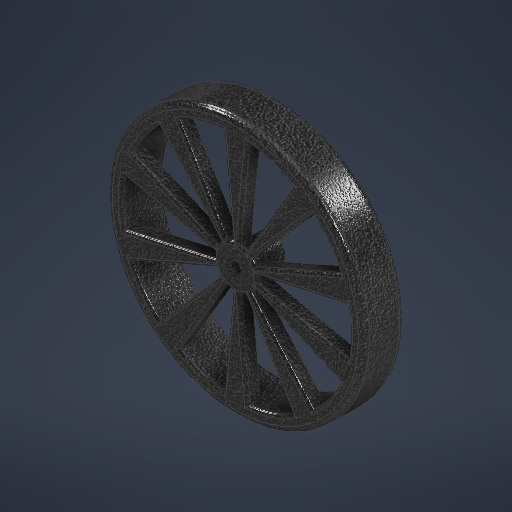
# Autodesk Inventor part: roues_3d_moteur_axe
Saved by Autodesk Inventor 2026 (Build 300175050, 175E)
## iProperties
Created: 2025-05-23
Part Number: roues_3d_moteur_axe
Material: Generisch
Document SubType Name: Modeling
Designer: karle
Density: 1 g/cm^3
Appearance: Vorgabe
Author: karle
Autodesk Inventor part; units mm, degrees
ref_plane "YZ Plane" through (0, 0, 0) normal (1, 0, 0) x (0, 1, 0)
sketch "Skizze1" plane through (0, 0, 0) normal (0, 0, 1) x (1, 0, 0)
  circle A0 centre (0, 0) radius 2
  circle A1 centre (0, 0) radius 45
  dimension "d0" = 4
  dimension "d1" = 90
  constraints: 2 centre point, 2 coincident
  measures "d0" diameter of A0
  measures "d1" diameter of A1
extrude "Extrusion1" add sketch "Skizze1" along normal mid plane 14.5
sketch "Skizze2" plane through (0, 0, -7.25) normal (0, 0, -1) x (-1, 0, 0)
  circle A0 centre (0, 0) radius 40
  circle A1 centre (0, 0) radius 5
  dimension "d4" = 10
  dimension "d5" = 80
  constraints: 2 centre point, 2 coincident
  measures "d4" diameter of A1
  measures "d5" diameter of A0
extrude "Extrusion2" cut sketch "Skizze2" against normal blind 10
sketch "Skizze3" plane through (0, 0, 7.25) normal (0, 0, 1) x (1, 0, 0)
  circle A0 centre (0, 0) radius 2 projected
  arc A1 (-7.4013, 1.213) -> (-7.4013, -1.213) centre (0, 0) ccw
  arc A2 (-39.1401, 8.2493) -> (-39.1401, -8.2493) centre (0, 0) ccw
  line L0 (-39.1401, 8.2493) -> (-7.4013, 1.213)
  line L1 (-7.4013, -1.213) -> (-39.1401, -8.2493)
  line L2 (0, 0) -> (-34.8454, 0)
  dimension "d8" = 80
  dimension "d9" = 15
  dimension "d12" = 25
  constraints: 6 end point, 4 point on circle, 2 centre point, 2 coincident, 1 horizontal, 1 other
  measures "d8" diameter of A2
  measures "d9" diameter of A1
  measures "d12" angle of L0 L1
extrude "Extrusion3" cut sketch "Skizze3" against normal blind 5 contours A1 L1 A2 L0
pattern_circular "Runde Anordnung1" count 10 over 360 about axis through (0, 0, -10) along (0, 0, 1) of "Extrusion3"
fillet "Rundung1" radius 1 40 edges at (-23.2707, 4.7311, 7.25) (-40, 0, 7.25) (-23.2707, -4.7311, 7.25) (-7.5, 0, 7.25) (-21.6073, 9.8506, 7.25) (-32.3607, 23.5114, 7.25) (-16.0455, 17.5057, 7.25) (-6.0676, 4.4084, 7.25) (-2.3176, 7.1329, 7.25) (-11.6906, 20.6697, 7.25) (-12.3607, 38.0423, 7.25) (-2.6915, 23.5937, 7.25) (2.6915, 23.5937, 7.25) (12.3607, 38.0423, 7.25) (11.6906, 20.6697, 7.25) (2.3176, 7.1329, 7.25) (16.0455, 17.5057, 7.25) (21.6073, 9.8506, 7.25) (6.0676, 4.4084, 7.25) (32.3607, 23.5114, 7.25) (40, 0, 7.25) (32.3607, -23.5114, 7.25) (21.6073, -9.8506, 7.25) (23.2707, -4.7311, 7.25) (23.2707, 4.7311, 7.25) (7.5, 0, 7.25) (6.0676, -4.4084, 7.25) (16.0455, -17.5057, 7.25) (11.6906, -20.6697, 7.25) (2.3176, -7.1329, 7.25) (2.6915, -23.5937, 7.25) (12.3607, -38.0423, 7.25) (-2.6915, -23.5937, 7.25) (-12.3607, -38.0423, 7.25) (-11.6906, -20.6697, 7.25) (-2.3176, -7.1329, 7.25) (-16.0455, -17.5057, 7.25) (-21.6073, -9.8506, 7.25) (-6.0676, -4.4084, 7.25) (-32.3607, -23.5114, 7.25)
sketch "Skizze4" plane through (0, 0, -7.25) normal (0, 0, -1) x (-1, 0, 0)
  circle A0 centre (0, 0) radius 7.5
  circle A1 centre (0, 0) radius 2
  dimension "d40" = 4
  dimension "d41" = 15
  constraints: 2 centre point, 2 coincident
  measures "d40" diameter of A1
  measures "d41" diameter of A0
extrude "Extrusion4" cut sketch "Skizze4" against normal blind 2
ref_plane "Arbeitsebene1" through (0, 5, -7.25) normal (0, 1, 0) x (-1, 0, 0)
ref_plane "Arbeitsebene2" through (0, 2, 0) normal (0, 1, 0) x (-1, 0, 0)
fillet "Rundung3" radius 2 2 edges at (-45, 0, 7.25) (-45, 0, -7.25)
